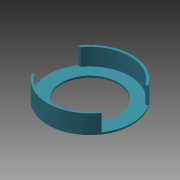
# Autodesk Inventor part: roll_body
Saved by Autodesk Inventor 2014 (Build 180170000, 170)
## iProperties
Created: 2014-09-19
Part Number: roll_body
Material: Všeobecné
Document SubType Name: Modeling
Designer: brodhaq
Density: 1 g/cm^3
Appearance: Výchozí
Author: brodhaq
Autodesk Inventor part; units mm, degrees
ref_plane "YZ Plane" through (0, 0, 0) normal (1, 0, 0) x (0, 1, 0)
ref_plane "XZ Plane" through (0, 0, 0) normal (0, 1, 0) x (-1, 0, 0)
ref_plane "XY Plane" through (0, 0, 0) normal (0, 0, 1) x (1, 0, 0)
sketch "Náčrt1" plane through (0, 0, 0) normal (0, 0, 1) x (1, 0, 0)
  circle A0 centre (0, 0) radius 37
  circle A1 centre (0, 0) radius 25
  arc A2 (-28.5, -20.3162) -> (28.5, -20.3162) centre (0, 0) ccw
  arc A3 (28.5, 20.3162) -> (-28.5, 20.3162) centre (0, 0) ccw
  line L0 (-28.5, -20.3162) -> (-30.5, -20.3162)
  line L1 (-28.5, 20.3162) -> (-30.5, 20.3162)
  line L2 (28.5, -20.3162) -> (30.5, -20.3162)
  line L3 (28.5, 20.3162) -> (30.5, 20.3162)
  line L4 (30.5, -20.9464) -> (30.5, -20.3162)
  line L5 (30.5, 20.3162) -> (30.5, 20.9464)
  line L6 (-30.5, 20.9464) -> (-30.5, 20.3162)
  line L7 (-30.5, -20.3162) -> (-30.5, -20.9464)
  dimension "d0" = 74
  dimension "d1" = 50
  dimension "d7" = 35
  dimension "d8" = 35
  constraints: 16 end point, 8 point on circle, 6 perpendicular, 5 parallel, 4 centre point, 3 coincident, 2 vertical
  measures "d0" diameter of A0
  measures "d1" diameter of A1
  measures "d7" radius of A3
  measures "d8" radius of A2
extrude "Vysunutí1" add sketch "Náčrt1" against normal blind 1.5
extrude "Vysunutí2" add sketch "Náčrt1" along normal blind 15 contours L5 L3 A3 L1 L6 A0
extrude "Vysunutí3" add sketch "Náčrt1" along normal blind 15 contours A0 L7 L0 A2 L2 L4
